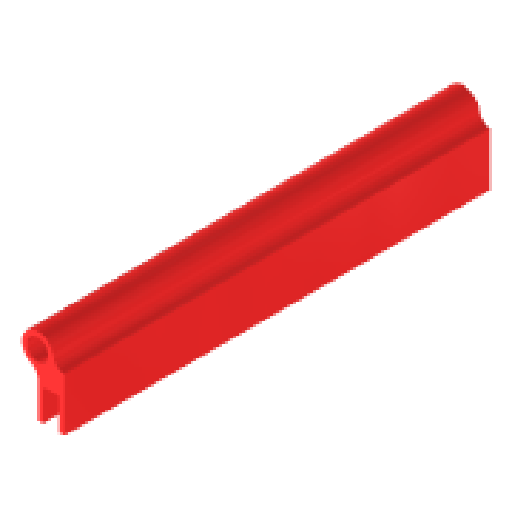
# Autodesk Inventor part: BISAGRA TAPA
Saved by Autodesk Inventor 2025.2 (Build 292293000, 293)
## iProperties
Created: 2026-09-20
Part Number: BISAGRA TAPA
Material: Plástico SAN
Document SubType Name: Modeling
Designer: autor
Density: 1.068 g/cm^3
Appearance: Rojo claro
Author: autor
Autodesk Inventor part; units mm, degrees
ref_plane "YZ Plane" through (0, 0, 0) normal (1, 0, 0) x (0, 1, 0)
ref_plane "XZ Plane" through (0, 0, 0) normal (0, 1, 0) x (-1, 0, 0)
ref_plane "XY Plane" through (0, 0, 0) normal (0, 0, 1) x (1, 0, 0)
sketch "Boceto1" plane through (0, 0, 0) normal (0, 0, 1) x (1, 0, 0)
  line L0 (-8.8278, -5.8719) -> (-8.8278, 2.6281)
  line L1 (-6.2298, 4.1281) -> (-3.8278, 4.1281)
  line L2 (-3.8278, 4.1281) -> (-3.8278, -5.8719)
  line L3 (-3.8278, -5.8719) -> (-4.8278, -5.8719)
  line L4 (-4.8278, -5.8719) -> (-4.8278, 0.1281)
  line L5 (-4.8278, 0.1281) -> (-7.8278, 0.1281)
  line L6 (-7.8278, 0.1281) -> (-7.8278, -5.8719)
  line L7 (-7.8278, -5.8719) -> (-8.8278, -5.8719)
  arc A0 (-6.2298, 4.1281) -> (-8.8278, 2.6281) centre (-8.8278, 5.6281) ccw
  circle A1 centre (-8.8278, 5.6281) radius 2
  arc A2 (-8.3944, 7.5806) -> (-6.8754, 5.1947) centre (-8.8278, 5.6281) ccw projected
  point P0 (0, 0)
  dimension "d2" = 10
  dimension "d3" = 1
  dimension "d4" = 6
  dimension "d5" = 3
  dimension "d6" = 6
  dimension "d7" = 4
  dimension "d8" = 5
  dimension "d9" = 10
  constraints: 16 end point, 5 perpendicular, 2 centre point, 2 point on circle, 1 coincident, 1 parallel, 1 point on line, 1 vertical
  measures "d2" distance of L1.end L2.end
  measures "d3" distance of L2.end L3.end
  measures "d4" distance of L3.end L4.end
  measures "d5" distance of L4.end L5.end
  measures "d6" diameter of A0
  measures "d7" diameter of A1
  measures "d8" distance between parallel lines of L2 L0
  measures "d9" distance between parallel lines of L1 L7
extrude "Extrusión1" add sketch "Boceto1" along normal blind 78
fillet "Empalme1" radius 2 2 edges at (-8.8278, 2.6281, 39) (-6.2298, 4.1281, 39)
fillet "Empalme2" radius 0.5 2 edges at (-4.8278, 0.1281, 39) (-7.8278, 0.1281, 39)
